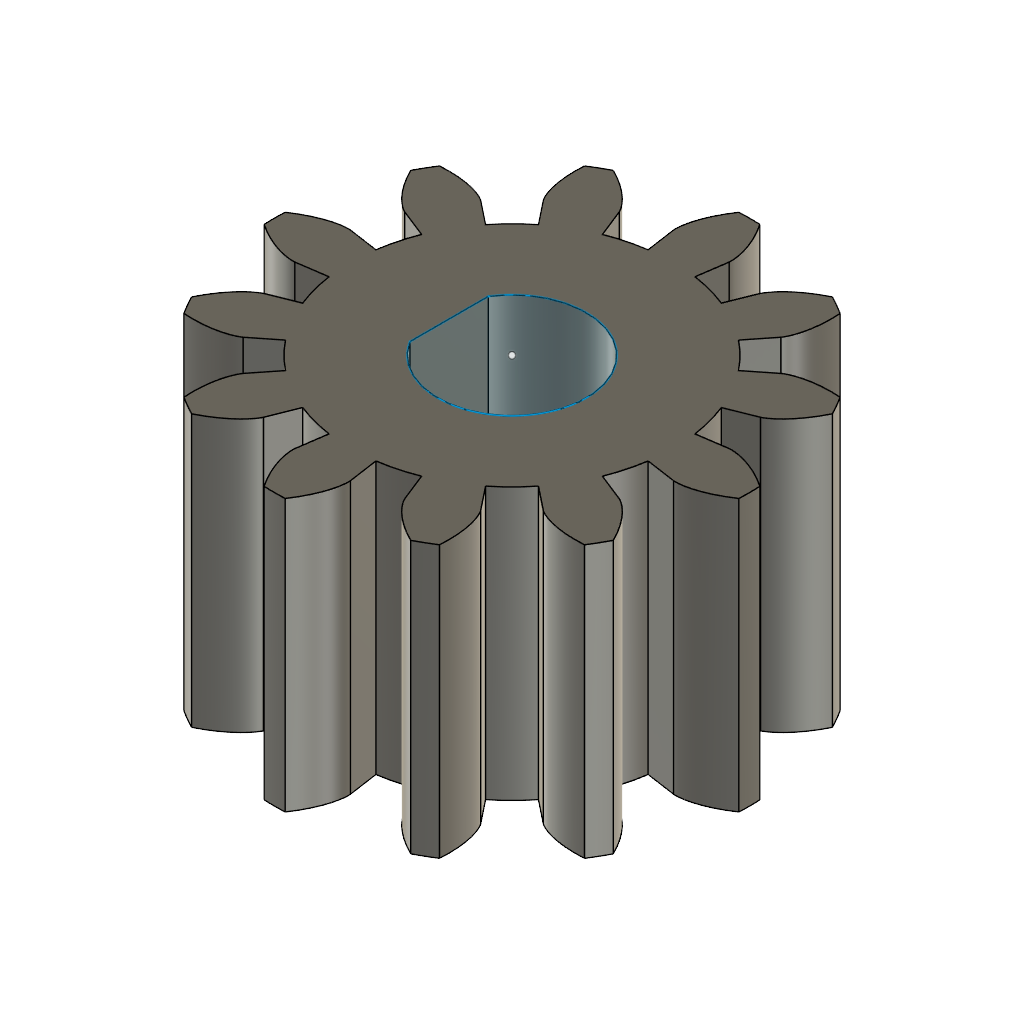
12T gear (Autodesk Fusion 360 design; units mm, degrees)
part number: 2026-11-12-16-14-20-707
Autodesk Fusion 360 part; units mm, degrees
sketch "Sketch1" plane through (0, 0, 0) normal (0, 0, 1) x (1, 0, 0)
  spline S0 degree 5 poles (8.3684, -1.2289) (8.3685, -1.2289) (8.3688, -1.2289) (8.3692, -1.229) (8.3697, -1.229) (8.3706, -1.2291) (8.3716, -1.2293) (8.3728, -1.2294) (8.374, -1.2295) (8.3754, -1.2297) (8.377, -1.2298) (8.3786, -1.23) (8.3804, -1.2301) (8.3823, -1.2303) (8.3844, -1.2305) (8.3865, -1.2307) (8.3888, -1.2308) (8.3912, -1.231) (8.3937, -1.2312) (8.3963, -1.2314) (8.399, -1.2315) (8.4019, -1.2317) (8.4048, -1.2318) (8.4079, -1.232) (8.4111, -1.2321) (8.4143, -1.2323) (8.4177, -1.2324) (8.4212, -1.2325) (8.4248, -1.2326) (8.4285, -1.2327) (8.4323, -1.2328) (8.4361, -1.2329) (8.4401, -1.233) (8.4442, -1.233) (8.4484, -1.2331) (8.4527, -1.2331) (8.457, -1.2331) (8.4615, -1.2331) (8.466, -1.2331) (8.4707, -1.233) (8.4754, -1.233) (8.4802, -1.2329) (8.4852, -1.2328) (8.4902, -1.2327) (8.4952, -1.2326) (8.5004, -1.2324) (8.5057, -1.2322) (8.511, -1.232) (8.5164, -1.2318) (8.5219, -1.2316) (8.5275, -1.2313) (8.5332, -1.231) (8.5389, -1.2307) (8.5448, -1.2304) (8.5507, -1.23) (8.5566, -1.2296) (8.5627, -1.2292) (8.5688, -1.2288) (8.575, -1.2283) (8.5813, -1.2278) (8.5877, -1.2273) (8.5941, -1.2268) (8.6006, -1.2262) (8.6072, -1.2256) (8.6138, -1.225) (8.6206, -1.2243) (8.6273, -1.2236) (8.6342, -1.2229) (8.6411, -1.2222) (8.6481, -1.2214) (8.6552, -1.2206) (8.6623, -1.2198) (8.6695, -1.2189) (8.6768, -1.218) (8.6841, -1.2171) (8.6915, -1.2161) (8.6989, -1.2151) (8.7064, -1.2141) (8.714, -1.213) (8.7216, -1.2119) (8.7293, -1.2108) (8.7371, -1.2096) (8.7449, -1.2084) (8.7528, -1.2072) (8.7608, -1.2059) (8.7688, -1.2046) (8.7768, -1.2033) (8.7849, -1.2019) (8.7931, -1.2005) (8.8013, -1.1991) (8.8096, -1.1976) (8.818, -1.1961) (8.8264, -1.1945) (8.8348, -1.1929) (8.8433, -1.1913) (8.8519, -1.1896) (8.8605, -1.1879) (8.8692, -1.1862) (8.8779, -1.1844) (8.8866, -1.1826) (8.8955, -1.1807) (8.9043, -1.1788) (8.9133, -1.1769) (8.9222, -1.1749) (8.9312, -1.1729) (8.9403, -1.1709) (8.9494, -1.1688) (8.9586, -1.1666) (8.9678, -1.1645) (8.9771, -1.1622) (8.9864, -1.16) (8.9958, -1.1577) (9.0052, -1.1554) (9.0146, -1.153) (9.0241, -1.1506) (9.0336, -1.1481) (9.0432, -1.1456) (9.0528, -1.1431) (9.0625, -1.1405) (9.0722, -1.1379) (9.082, -1.1352) (9.0918, -1.1325) (9.1016, -1.1298) (9.1115, -1.127) (9.1214, -1.1242) (9.1314, -1.1213) (9.1414, -1.1184) (9.1514, -1.1154) (9.1615, -1.1124) (9.1716, -1.1093) (9.1818, -1.1063) (9.192, -1.1031) (9.2023, -1.0999) (9.2125, -1.0967) (9.2228, -1.0935) (9.2332, -1.0901) (9.2436, -1.0868) (9.254, -1.0834) (9.2645, -1.08) (9.275, -1.0765) (9.2855, -1.0729) (9.2961, -1.0694) (9.3067, -1.0657) (9.3173, -1.0621) (9.328, -1.0584) (9.3387, -1.0546) (9.3494, -1.0508) (9.3602, -1.047) (9.371, -1.0431) (9.3818, -1.0391) (9.3927, -1.0351) (9.4036, -1.0311) (9.4145, -1.027) (9.4255, -1.0229) (9.4365, -1.0188) (9.4475, -1.0146) (9.4585, -1.0103) (9.4696, -1.006) (9.4807, -1.0016) (9.4919, -0.9972) (9.503, -0.9928) (9.5142, -0.9883) (9.5255, -0.9838) (9.5367, -0.9792) (9.548, -0.9746) (9.5593, -0.9699) (9.5706, -0.9652) (9.582, -0.9604) (9.5934, -0.9556) (9.6048, -0.9507) (9.6162, -0.9458) (9.6277, -0.9409) (9.6392, -0.9358) (9.6507, -0.9308) (9.6623, -0.9257) (9.6738, -0.9206) (9.6854, -0.9154) (9.697, -0.9101) (9.7087, -0.9048) (9.7203, -0.8995) (9.732, -0.8941) (9.7437, -0.8887) (9.7554, -0.8832) (9.7672, -0.8777) (9.7789, -0.8721) (9.7907, -0.8665) (9.8025, -0.8608) (9.8144, -0.8551) (9.8262, -0.8493) (9.8381, -0.8435) (9.85, -0.8376) (9.8619, -0.8317) (9.8738, -0.8257) (9.8858, -0.8197) (9.8977, -0.8137) (9.9097, -0.8076) (9.9217, -0.8014) (9.9338, -0.7952) (9.9458, -0.789) (9.9579, -0.7827) (9.97, -0.7763) (9.9821, -0.7699) (9.9942, -0.7635) (10.0063, -0.757) (10.0184, -0.7504) (10.0306, -0.7438) (10.0428, -0.7372) (10.055, -0.7305) (10.0672, -0.7238) (10.0794, -0.717) (10.0916, -0.7102) (10.1039, -0.7033) (10.1162, -0.6963) (10.1284, -0.6894) (10.1407, -0.6823) (10.153, -0.6752) (10.1654, -0.6681) (10.1777, -0.6609) (10.1901, -0.6537) (10.2024, -0.6464) (10.2148, -0.6391) (10.2272, -0.6317) (10.2396, -0.6243) (10.252, -0.6168) (10.2644, -0.6093) (10.2768, -0.6018) (10.2893, -0.5941) (10.3017, -0.5865) (10.3142, -0.5787) (10.3267, -0.571) (10.3392, -0.5632) (10.3516, -0.5553) (10.3642, -0.5474) (10.3767, -0.5394) (10.3892, -0.5314) (10.4017, -0.5233) (10.4143, -0.5152) (10.4268, -0.5071) (10.4394, -0.4989) (10.4519, -0.4906) (10.4645, -0.4823) (10.4746, -0.4756) (10.4821, -0.4706) (10.4872, -0.4672) (10.4897, -0.4655) knots 0 0 0 0 0 0 0.00416667 0.00833333 0.0125 0.01666667 0.02083333 0.025 0.02916667 0.03333333 0.0375 0.04166667 0.04583333 0.05 0.05416667 0.05833333 0.0625 0.06666667 0.07083333 0.075 0.07916667 0.08333333 0.0875 0.09166667 0.09583333 0.1 0.10416667 0.10833333 0.1125 0.11666667 0.12083333 0.125 0.12916667 0.13333333 0.1375 0.14166667 0.14583333 0.15 0.15416667 0.15833333 0.1625 0.16666667 0.17083333 0.175 0.17916667 0.18333333 0.1875 0.19166667 0.19583333 0.2 0.20416667 0.20833333 0.2125 0.21666667 0.22083333 0.225 0.22916667 0.23333333 0.2375 0.24166667 0.24583333 0.25 0.25416667 0.25833333 0.2625 0.26666667 0.27083333 0.275 0.27916667 0.28333333 0.2875 0.29166667 0.29583333 0.3 0.30416667 0.30833333 0.3125 0.31666667 0.32083333 0.325 0.32916667 0.33333333 0.3375 0.34166667 0.34583333 0.35 0.35416667 0.35833333 0.3625 0.36666667 0.37083333 0.375 0.37916667 0.38333333 0.3875 0.39166667 0.39583333 0.4 0.40416667 0.40833333 0.4125 0.41666667 0.42083333 0.425 0.42916667 0.43333333 0.4375 0.44166667 0.44583333 0.45 0.45416667 0.45833333 0.4625 0.46666667 0.47083333 0.475 0.47916667 0.48333333 0.4875 0.49166667 0.49583333 0.5 0.50416667 0.50833333 0.5125 0.51666667 0.52083333 0.525 0.52916667 0.53333333 0.5375 0.54166667 0.54583333 0.55 0.55416667 0.55833333 0.5625 0.56666667 0.57083333 0.575 0.57916667 0.58333333 0.5875 0.59166667 0.59583333 0.6 0.60416667 0.60833333 0.6125 0.61666667 0.62083333 0.625 0.62916667 0.63333333 0.6375 0.64166667 0.64583333 0.65 0.65416667 0.65833333 0.6625 0.66666667 0.67083333 0.675 0.67916667 0.68333333 0.6875 0.69166667 0.69583333 0.7 0.70416667 0.70833333 0.7125 0.71666667 0.72083333 0.725 0.72916667 0.73333333 0.7375 0.74166667 0.74583333 0.75 0.75416667 0.75833333 0.7625 0.76666667 0.77083333 0.775 0.77916667 0.78333333 0.7875 0.79166667 0.79583333 0.8 0.80416667 0.80833333 0.8125 0.81666667 0.82083333 0.825 0.82916667 0.83333333 0.8375 0.84166667 0.84583333 0.85 0.85416667 0.85833333 0.8625 0.86666667 0.87083333 0.875 0.87916667 0.88333333 0.8875 0.89166667 0.89583333 0.9 0.90416667 0.90833333 0.9125 0.91666667 0.92083333 0.925 0.92916667 0.93333333 0.9375 0.94166667 0.94583333 0.95 0.95416667 0.95833333 0.9625 0.96666667 0.97083333 0.975 0.97916667 0.98333333 0.9875 0.99166667 0.99583333 1 1 1 1 1 1
  spline S1 degree 5 poles (8.3684, 1.2289) (8.3685, 1.2289) (8.3688, 1.2289) (8.3692, 1.229) (8.3697, 1.229) (8.3706, 1.2291) (8.3716, 1.2293) (8.3728, 1.2294) (8.374, 1.2295) (8.3754, 1.2297) (8.377, 1.2298) (8.3786, 1.23) (8.3804, 1.2301) (8.3823, 1.2303) (8.3844, 1.2305) (8.3865, 1.2307) (8.3888, 1.2308) (8.3912, 1.231) (8.3937, 1.2312) (8.3963, 1.2314) (8.399, 1.2315) (8.4019, 1.2317) (8.4048, 1.2318) (8.4079, 1.232) (8.4111, 1.2321) (8.4143, 1.2323) (8.4177, 1.2324) (8.4212, 1.2325) (8.4248, 1.2326) (8.4285, 1.2327) (8.4323, 1.2328) (8.4361, 1.2329) (8.4401, 1.233) (8.4442, 1.233) (8.4484, 1.2331) (8.4527, 1.2331) (8.457, 1.2331) (8.4615, 1.2331) (8.466, 1.2331) (8.4707, 1.233) (8.4754, 1.233) (8.4802, 1.2329) (8.4852, 1.2328) (8.4902, 1.2327) (8.4952, 1.2326) (8.5004, 1.2324) (8.5057, 1.2322) (8.511, 1.232) (8.5164, 1.2318) (8.5219, 1.2316) (8.5275, 1.2313) (8.5332, 1.231) (8.5389, 1.2307) (8.5448, 1.2304) (8.5507, 1.23) (8.5566, 1.2296) (8.5627, 1.2292) (8.5688, 1.2288) (8.575, 1.2283) (8.5813, 1.2278) (8.5877, 1.2273) (8.5941, 1.2268) (8.6006, 1.2262) (8.6072, 1.2256) (8.6138, 1.225) (8.6206, 1.2243) (8.6273, 1.2236) (8.6342, 1.2229) (8.6411, 1.2222) (8.6481, 1.2214) (8.6552, 1.2206) (8.6623, 1.2198) (8.6695, 1.2189) (8.6768, 1.218) (8.6841, 1.2171) (8.6915, 1.2161) (8.6989, 1.2151) (8.7064, 1.2141) (8.714, 1.213) (8.7216, 1.2119) (8.7293, 1.2108) (8.7371, 1.2096) (8.7449, 1.2084) (8.7528, 1.2072) (8.7608, 1.2059) (8.7688, 1.2046) (8.7768, 1.2033) (8.7849, 1.2019) (8.7931, 1.2005) (8.8013, 1.1991) (8.8096, 1.1976) (8.818, 1.1961) (8.8264, 1.1945) (8.8348, 1.1929) (8.8433, 1.1913) (8.8519, 1.1896) (8.8605, 1.1879) (8.8692, 1.1862) (8.8779, 1.1844) (8.8866, 1.1826) (8.8955, 1.1807) (8.9043, 1.1788) (8.9133, 1.1769) (8.9222, 1.1749) (8.9312, 1.1729) (8.9403, 1.1709) (8.9494, 1.1688) (8.9586, 1.1666) (8.9678, 1.1645) (8.9771, 1.1622) (8.9864, 1.16) (8.9958, 1.1577) (9.0052, 1.1554) (9.0146, 1.153) (9.0241, 1.1506) (9.0336, 1.1481) (9.0432, 1.1456) (9.0528, 1.1431) (9.0625, 1.1405) (9.0722, 1.1379) (9.082, 1.1352) (9.0918, 1.1325) (9.1016, 1.1298) (9.1115, 1.127) (9.1214, 1.1242) (9.1314, 1.1213) (9.1414, 1.1184) (9.1514, 1.1154) (9.1615, 1.1124) (9.1716, 1.1093) (9.1818, 1.1063) (9.192, 1.1031) (9.2023, 1.0999) (9.2125, 1.0967) (9.2228, 1.0935) (9.2332, 1.0901) (9.2436, 1.0868) (9.254, 1.0834) (9.2645, 1.08) (9.275, 1.0765) (9.2855, 1.0729) (9.2961, 1.0694) (9.3067, 1.0657) (9.3173, 1.0621) (9.328, 1.0584) (9.3387, 1.0546) (9.3494, 1.0508) (9.3602, 1.047) (9.371, 1.0431) (9.3818, 1.0391) (9.3927, 1.0351) (9.4036, 1.0311) (9.4145, 1.027) (9.4255, 1.0229) (9.4365, 1.0188) (9.4475, 1.0146) (9.4585, 1.0103) (9.4696, 1.006) (9.4807, 1.0016) (9.4919, 0.9972) (9.503, 0.9928) (9.5142, 0.9883) (9.5255, 0.9838) (9.5367, 0.9792) (9.548, 0.9746) (9.5593, 0.9699) (9.5706, 0.9652) (9.582, 0.9604) (9.5934, 0.9556) (9.6048, 0.9507) (9.6162, 0.9458) (9.6277, 0.9409) (9.6392, 0.9358) (9.6507, 0.9308) (9.6623, 0.9257) (9.6738, 0.9206) (9.6854, 0.9154) (9.697, 0.9101) (9.7087, 0.9048) (9.7203, 0.8995) (9.732, 0.8941) (9.7437, 0.8887) (9.7554, 0.8832) (9.7672, 0.8777) (9.7789, 0.8721) (9.7907, 0.8665) (9.8025, 0.8608) (9.8144, 0.8551) (9.8262, 0.8493) (9.8381, 0.8435) (9.85, 0.8376) (9.8619, 0.8317) (9.8738, 0.8257) (9.8858, 0.8197) (9.8977, 0.8137) (9.9097, 0.8076) (9.9217, 0.8014) (9.9338, 0.7952) (9.9458, 0.789) (9.9579, 0.7827) (9.97, 0.7763) (9.9821, 0.7699) (9.9942, 0.7635) (10.0063, 0.757) (10.0184, 0.7504) (10.0306, 0.7438) (10.0428, 0.7372) (10.055, 0.7305) (10.0672, 0.7238) (10.0794, 0.717) (10.0916, 0.7102) (10.1039, 0.7033) (10.1162, 0.6963) (10.1284, 0.6894) (10.1407, 0.6823) (10.153, 0.6752) (10.1654, 0.6681) (10.1777, 0.6609) (10.1901, 0.6537) (10.2024, 0.6464) (10.2148, 0.6391) (10.2272, 0.6317) (10.2396, 0.6243) (10.252, 0.6168) (10.2644, 0.6093) (10.2768, 0.6018) (10.2893, 0.5941) (10.3017, 0.5865) (10.3142, 0.5787) (10.3267, 0.571) (10.3392, 0.5632) (10.3516, 0.5553) (10.3642, 0.5474) (10.3767, 0.5394) (10.3892, 0.5314) (10.4017, 0.5233) (10.4143, 0.5152) (10.4268, 0.5071) (10.4394, 0.4989) (10.4519, 0.4906) (10.4645, 0.4823) (10.4746, 0.4756) (10.4821, 0.4706) (10.4872, 0.4672) (10.4897, 0.4655) knots 0 0 0 0 0 0 0.00416667 0.00833333 0.0125 0.01666667 0.02083333 0.025 0.02916667 0.03333333 0.0375 0.04166667 0.04583333 0.05 0.05416667 0.05833333 0.0625 0.06666667 0.07083333 0.075 0.07916667 0.08333333 0.0875 0.09166667 0.09583333 0.1 0.10416667 0.10833333 0.1125 0.11666667 0.12083333 0.125 0.12916667 0.13333333 0.1375 0.14166667 0.14583333 0.15 0.15416667 0.15833333 0.1625 0.16666667 0.17083333 0.175 0.17916667 0.18333333 0.1875 0.19166667 0.19583333 0.2 0.20416667 0.20833333 0.2125 0.21666667 0.22083333 0.225 0.22916667 0.23333333 0.2375 0.24166667 0.24583333 0.25 0.25416667 0.25833333 0.2625 0.26666667 0.27083333 0.275 0.27916667 0.28333333 0.2875 0.29166667 0.29583333 0.3 0.30416667 0.30833333 0.3125 0.31666667 0.32083333 0.325 0.32916667 0.33333333 0.3375 0.34166667 0.34583333 0.35 0.35416667 0.35833333 0.3625 0.36666667 0.37083333 0.375 0.37916667 0.38333333 0.3875 0.39166667 0.39583333 0.4 0.40416667 0.40833333 0.4125 0.41666667 0.42083333 0.425 0.42916667 0.43333333 0.4375 0.44166667 0.44583333 0.45 0.45416667 0.45833333 0.4625 0.46666667 0.47083333 0.475 0.47916667 0.48333333 0.4875 0.49166667 0.49583333 0.5 0.50416667 0.50833333 0.5125 0.51666667 0.52083333 0.525 0.52916667 0.53333333 0.5375 0.54166667 0.54583333 0.55 0.55416667 0.55833333 0.5625 0.56666667 0.57083333 0.575 0.57916667 0.58333333 0.5875 0.59166667 0.59583333 0.6 0.60416667 0.60833333 0.6125 0.61666667 0.62083333 0.625 0.62916667 0.63333333 0.6375 0.64166667 0.64583333 0.65 0.65416667 0.65833333 0.6625 0.66666667 0.67083333 0.675 0.67916667 0.68333333 0.6875 0.69166667 0.69583333 0.7 0.70416667 0.70833333 0.7125 0.71666667 0.72083333 0.725 0.72916667 0.73333333 0.7375 0.74166667 0.74583333 0.75 0.75416667 0.75833333 0.7625 0.76666667 0.77083333 0.775 0.77916667 0.78333333 0.7875 0.79166667 0.79583333 0.8 0.80416667 0.80833333 0.8125 0.81666667 0.82083333 0.825 0.82916667 0.83333333 0.8375 0.84166667 0.84583333 0.85 0.85416667 0.85833333 0.8625 0.86666667 0.87083333 0.875 0.87916667 0.88333333 0.8875 0.89166667 0.89583333 0.9 0.90416667 0.90833333 0.9125 0.91666667 0.92083333 0.925 0.92916667 0.93333333 0.9375 0.94166667 0.94583333 0.95 0.95416667 0.95833333 0.9625 0.96666667 0.97083333 0.975 0.97916667 0.98333333 0.9875 0.99166667 0.99583333 1 1 1 1 1 1
  spline S2 degree 5 poles (8.3675, -1.2287) (8.3675, -1.2287) (8.3676, -1.2288) (8.3677, -1.2288) (8.3679, -1.2288) (8.3681, -1.2288) (8.3682, -1.2288) (8.3683, -1.2288) (8.3684, -1.2289) (8.3684, -1.2289) knots 0 0 0 0 0 0 0.2 0.4 0.6 0.8 1 1 1 1 1 1
  spline S3 degree 5 poles (8.3675, 1.2287) (8.3675, 1.2287) (8.3676, 1.2288) (8.3677, 1.2288) (8.3679, 1.2288) (8.3681, 1.2288) (8.3682, 1.2288) (8.3683, 1.2288) (8.3684, 1.2289) (8.3684, 1.2289) knots 0 0 0 0 0 0 0.2 0.4 0.6 0.8 1 1 1 1 1 1
  line L0 (0, 0) -> (8.3675, -1.2287)
  line L1 (0, 0) -> (8.3675, 1.2287)
  arc A0 (10.4897, -0.4655) -> (10.4897, 0.4655) centre (0, 0) ccw
  point P0 (8.3713, -1.2292)
  point P1 (8.376, -1.2297)
  point P2 (8.3827, -1.2303)
  point P3 (8.3912, -1.231)
  point P4 (8.4017, -1.2317)
  point P5 (8.4141, -1.2323)
  point P6 (8.4284, -1.2327)
  point P7 (8.4446, -1.233)
  point P8 (8.4627, -1.2331)
  point P9 (8.4827, -1.2328)
  point P10 (8.5046, -1.2323)
  point P11 (8.5285, -1.2313)
  point P12 (8.5542, -1.2298)
  point P13 (8.5817, -1.2278)
  point P14 (8.6112, -1.2252)
  point P15 (8.6425, -1.222)
  point P16 (8.6756, -1.2181)
  point P17 (8.7106, -1.2135)
  point P18 (8.7474, -1.208)
  point P19 (8.786, -1.2017)
  point P20 (8.8263, -1.1945)
  point P21 (8.8685, -1.1863)
  point P22 (8.9123, -1.1771)
  point P23 (8.9579, -1.1668)
  point P24 (9.0052, -1.1554)
  point P25 (9.0541, -1.1428)
  point P26 (9.1047, -1.1289)
  point P27 (9.1569, -1.1138)
  point P28 (9.2107, -1.0973)
  point P29 (9.266, -1.0794)
  point P30 (9.3229, -1.0601)
  point P31 (9.3813, -1.0393)
  point P32 (9.4412, -1.017)
  point P33 (9.5024, -0.993)
  point P34 (9.5651, -0.9675)
  point P35 (9.6292, -0.9402)
  point P36 (9.6946, -0.9112)
  point P37 (9.7612, -0.8805)
  point P38 (9.8291, -0.8479)
  point P39 (9.8983, -0.8134)
  point P40 (9.9686, -0.777)
  point P41 (10.04, -0.7387)
  point P42 (10.1125, -0.6984)
  point P43 (10.186, -0.6561)
  point P44 (10.2606, -0.6116)
  point P45 (10.3361, -0.5651)
  point P46 (10.4124, -0.5164)
  point P47 (8.3713, 1.2292)
  point P48 (8.376, 1.2297)
  point P49 (8.3827, 1.2303)
  point P50 (8.3912, 1.231)
  point P51 (8.4017, 1.2317)
  point P52 (8.4141, 1.2323)
  point P53 (8.4284, 1.2327)
  point P54 (8.4446, 1.233)
  point P55 (8.4627, 1.2331)
  point P56 (8.4827, 1.2328)
  point P57 (8.5046, 1.2323)
  point P58 (8.5285, 1.2313)
  point P59 (8.5542, 1.2298)
  point P60 (8.5817, 1.2278)
  point P61 (8.6112, 1.2252)
  point P62 (8.6425, 1.222)
  point P63 (8.6756, 1.2181)
  point P64 (8.7106, 1.2135)
  point P65 (8.7474, 1.208)
  point P66 (8.786, 1.2017)
  point P67 (8.8263, 1.1945)
  point P68 (8.8685, 1.1863)
  point P69 (8.9123, 1.1771)
  point P70 (8.9579, 1.1668)
  point P71 (9.0052, 1.1554)
  point P72 (9.0541, 1.1428)
  point P73 (9.1047, 1.1289)
  point P74 (9.1569, 1.1138)
  point P75 (9.2107, 1.0973)
  point P76 (9.266, 1.0794)
  point P77 (9.3229, 1.0601)
  point P78 (9.3813, 1.0393)
  point P79 (9.4412, 1.017)
  point P80 (9.5024, 0.993)
  point P81 (9.5651, 0.9675)
  point P82 (9.6292, 0.9402)
  point P83 (9.6946, 0.9112)
  point P84 (9.7612, 0.8805)
  point P85 (9.8291, 0.8479)
  point P86 (9.8983, 0.8134)
  point P87 (9.9686, 0.777)
  point P88 (10.04, 0.7387)
  point P89 (10.1125, 0.6984)
  point P90 (10.186, 0.6561)
  point P91 (10.2606, 0.6116)
  point P92 (10.3361, 0.5651)
  point P93 (10.4124, 0.5164)
sketch "Sketch2" plane through (0, 0, 0) normal (0, 0, 1) x (1, 0, 0)
  circle A0 centre (0, 0) radius 7.125
extrude "Extrude1" add sketch "Sketch2" along normal blind 12 makes body 1
extrude "Extrude2" add sketch "Sketch1" along normal blind 12 separate body makes body 2
pattern_circular "C-Pattern1" count 12 over 360 about axis through (0, 0, 1.75) along (0, 0, 1) of "Extrude2" makes body 3 at (2.6206, 1.04, 4) makes body 4 at (1.04, 2.6206, 4) makes body 5 at (0.4096, 2.7895, 4) makes body 6 at (-1.04, 2.6206, 4) makes body 7 at (-2.211, 1.7495, 4) makes body 8 at (-2.7895, 0.4096, 4) makes body 9 at (-2.6206, -1.04, 4) makes body 10 at (-1.04, -2.6206, 4) makes body 11 at (-0.4096, -2.7895, 4) makes body 12 at (1.04, -2.6206, 4) makes body 13 at (2.211, -1.7495, 4)
combine "Combine1" operation add target body 1 tool bodies 2 3 4 5 6 7 8 9 10 11 12 13
sketch "Sketch3" plane through (0, 0, 0) normal (0, 0, 1) x (1, 0, 0)
  line L0 (0, 0) -> (50.7993, 0) construction
  line L1 (50.7993, 0) -> (50.7993, 3) construction
  line L2 (50.7993, 3) -> (0, 3) construction
  line L3 (0, 3) -> (0, 0) construction
  constraint perpendicular L0 L1
  constraint parallel L0 L2
  constraint parallel L1 L3
sketch "sketch 1072" plane through (0, 0, 12) normal (0, 0, 1) x (-1, 0, 0)
  line L0 (2.78, -1.7312) -> (2.78, 1.7312)
  arc A0 (2.78, 1.7312) -> (2.78, -1.7312) centre (0, 0) ccw
extrude "Extrude3" cut sketch "sketch 1072" against normal blind 12 bodies 1
